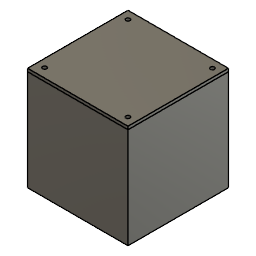
cubesat (Autodesk Fusion 360 design; units mm, degrees)
part number: 2026-02-11-22-36-21-555
Autodesk Fusion 360 part; units mm, degrees
sketch "Sketch1" plane through (0, 0, 0) normal (0, 1, 0) x (1, 0, 0)
  line L0 (15.6661, 100.8821) -> (115.6661, 100.8821)
  line L1 (115.6661, 100.8821) -> (115.6661, 0.8821)
  line L2 (115.6661, 0.8821) -> (15.6661, 0.8821)
  line L3 (15.6661, 0.8821) -> (15.6661, 100.8821)
  dimension "d1" = 100
  dimension "d2" = 100
  constraint horizontal L0
  constraint vertical L1
  constraint horizontal L2
  constraint vertical L3
  measures "d1" distance of L0.start L0.end
  measures "d2" distance of L0.start L2.end
extrude "Extrude1" add sketch "Sketch1" along normal blind 100 makes body 1
shell "Shell1" thickness 3 removed faces 1 at (48.9995, 100, -67.5488) on bodies 1
sketch "Sketch2" plane through (0, 0, 0) normal (0, 1, 0) x (1, 0, 0)
sketch "Sketch3" plane through (0, 3, 0) normal (0, 1, 0) x (-1, 0, 0)
  line L0 (-18.6661, -3.8821) -> (-112.6661, -3.8821)
  line L1 (-112.6661, -3.8821) -> (-112.6661, -97.8821)
  line L2 (-112.6661, -97.8821) -> (-18.6661, -97.8821)
  line L3 (-18.6661, -97.8821) -> (-18.6661, -3.8821)
  line L4 (-18.6661, -97.8821) -> (-28.6661, -97.8821)
  line L5 (-28.6661, -97.8821) -> (-28.6661, -87.8821)
  line L6 (-28.6661, -87.8821) -> (-18.6661, -87.8821)
  line L7 (-18.6661, -87.8821) -> (-18.6661, -97.8821)
  line L8 (-112.6661, -97.8821) -> (-102.6661, -97.8821)
  line L9 (-102.6661, -97.8821) -> (-102.6661, -87.8821)
  line L10 (-102.6661, -87.8821) -> (-112.6661, -87.8821)
  line L11 (-112.6661, -87.8821) -> (-112.6661, -97.8821)
  line L12 (-112.6661, -3.8821) -> (-102.6661, -3.8821)
  line L13 (-102.6661, -3.8821) -> (-102.6661, -13.8821)
  line L14 (-102.6661, -13.8821) -> (-112.6661, -13.8821)
  line L15 (-112.6661, -13.8821) -> (-112.6661, -3.8821)
  line L16 (-18.6661, -3.8821) -> (-28.6661, -3.8821)
  line L17 (-28.6661, -3.8821) -> (-28.6661, -13.8821)
  line L18 (-28.6661, -13.8821) -> (-18.6661, -13.8821)
  line L19 (-18.6661, -13.8821) -> (-18.6661, -3.8821)
  dimension "d6" = 10
  dimension "d7" = 10
  dimension "d8" = 10
  dimension "d9" = 10
  dimension "d10" = 10
  dimension "d11" = 10
  dimension "d12" = 10
  dimension "d13" = 10
  constraint horizontal L4
  constraint vertical L5
  constraint horizontal L6
  constraint vertical L7
  constraint coincident L2.end L3.start
  constraint horizontal L8
  constraint vertical L9
  constraint horizontal L10
  constraint vertical L11
  constraint coincident L1.end L2.start
  constraint horizontal L12
  constraint vertical L13
  constraint horizontal L14
  constraint vertical L15
  constraint coincident L0.end L1.start
  constraint horizontal L16
  constraint vertical L17
  constraint horizontal L18
  constraint vertical L19
  constraint coincident L0.start L3.end
  measures "d6" distance of L2.end L4.end
  measures "d7" distance of L2.end L6.end
  measures "d8" distance of L1.end L8.end
  measures "d9" distance of L1.end L10.end
  measures "d10" distance of L0.end L12.end
  measures "d11" distance of L0.end L14.end
  measures "d12" distance of L0.start L16.end
  measures "d13" distance of L0.start L18.end
extrude "Extrude2" add sketch "Sketch3" along normal blind 97 contours L0 L3 L16 L17 L18 L19 | L0 L1 L12 L13 L14 L15 | L2 L3 L4 L5 L6 L7 | L1 L2 L8 L9 L10 L11 bodies 1
sketch "Sketch4" plane through (0, 100, 0) normal (0, 1, 0) x (-1, 0, 0)
  line L0 (-18.6661, -13.8821) -> (-18.6661, -87.8821)
  line L1 (-18.6661, -87.8821) -> (-28.6661, -87.8821)
  line L2 (-28.6661, -87.8821) -> (-28.6661, -97.8821)
  line L3 (-28.6661, -97.8821) -> (-102.6661, -97.8821)
  line L4 (-102.6661, -97.8821) -> (-102.6661, -87.8821)
  line L5 (-102.6661, -87.8821) -> (-112.6661, -87.8821)
  line L6 (-112.6661, -87.8821) -> (-112.6661, -13.8821)
  line L7 (-112.6661, -13.8821) -> (-102.6661, -13.8821)
  line L8 (-102.6661, -13.8821) -> (-102.6661, -3.8821)
  line L9 (-102.6661, -3.8821) -> (-28.6661, -3.8821)
  line L10 (-28.6661, -3.8821) -> (-28.6661, -13.8821)
  line L11 (-28.6661, -13.8821) -> (-18.6661, -13.8821)
  line L12 (-15.6661, -0.8821) -> (-115.6661, -0.8821)
  line L13 (-115.6661, -0.8821) -> (-115.6661, -100.8821)
  line L14 (-115.6661, -100.8821) -> (-15.6661, -100.8821)
  line L15 (-15.6661, -100.8821) -> (-15.6661, -0.8821)
  circle A0 centre (-23.6661, -9.9068) radius 2
  circle A1 centre (-23.6661, -92.8821) radius 2
  circle A2 centre (-107.6661, -92.8821) radius 2
  circle A3 centre (-107.6661, -8.8821) radius 2
  dimension "d16" = 4
  dimension "d17" = 4
  dimension "d18" = 4
  dimension "d19" = 4
  measures "d16" diameter of A0
  measures "d17" diameter of A1
  measures "d18" diameter of A2
  measures "d19" diameter of A3
extrude "Extrude3" cut sketch "Sketch4" against normal blind 40 contours A0 | A1 | A2 | A3 bodies 1
sketch "Sketch5" plane through (0, 100, 0) normal (0, 1, 0) x (-1, 0, 0)
  circle A0 centre (-107.6661, -92.8821) radius 2
  circle A1 centre (-107.6661, -8.8821) radius 2
  circle A2 centre (-23.6661, -92.8821) radius 2
  circle A3 centre (-23.6661, -9.9068) radius 2
  line L0 (-18.6661, -13.8821) -> (-18.6661, -87.8821)
  line L1 (-18.6661, -87.8821) -> (-28.6661, -87.8821)
  line L2 (-28.6661, -87.8821) -> (-28.6661, -97.8821)
  line L3 (-28.6661, -97.8821) -> (-102.6661, -97.8821)
  line L4 (-102.6661, -97.8821) -> (-102.6661, -87.8821)
  line L5 (-102.6661, -87.8821) -> (-112.6661, -87.8821)
  line L6 (-112.6661, -87.8821) -> (-112.6661, -13.8821)
  line L7 (-112.6661, -13.8821) -> (-102.6661, -13.8821)
  line L8 (-102.6661, -13.8821) -> (-102.6661, -3.8821)
  line L9 (-102.6661, -3.8821) -> (-28.6661, -3.8821)
  line L10 (-28.6661, -3.8821) -> (-28.6661, -13.8821)
  line L11 (-28.6661, -13.8821) -> (-18.6661, -13.8821)
  line L12 (-15.6661, -0.8821) -> (-115.6661, -0.8821)
  line L13 (-115.6661, -0.8821) -> (-115.6661, -100.8821)
  line L14 (-115.6661, -100.8821) -> (-15.6661, -100.8821)
  line L15 (-15.6661, -100.8821) -> (-15.6661, -0.8821)
  line L16 (-15.6661, -100.8821) -> (-115.6661, -100.8821)
  line L17 (-115.6661, -100.8821) -> (-115.6661, -0.8821)
  line L18 (-115.6661, -0.8821) -> (-15.6661, -0.8821)
  line L19 (-15.6661, -0.8821) -> (-15.6661, -100.8821)
  constraint horizontal L16
  constraint vertical L17
  constraint horizontal L18
  constraint vertical L19
  constraint coincident L12.end L13.start
  constraint coincident L14.end L15.start
extrude "Extrude4" add sketch "Sketch5" along normal blind 3 separate body contours L0 L1 L2 L3 L4 L5 L6 L7 L8 L9 L10 L11 | L12 L13 L14 L15 L16 L17 L18 L19 makes body 2
